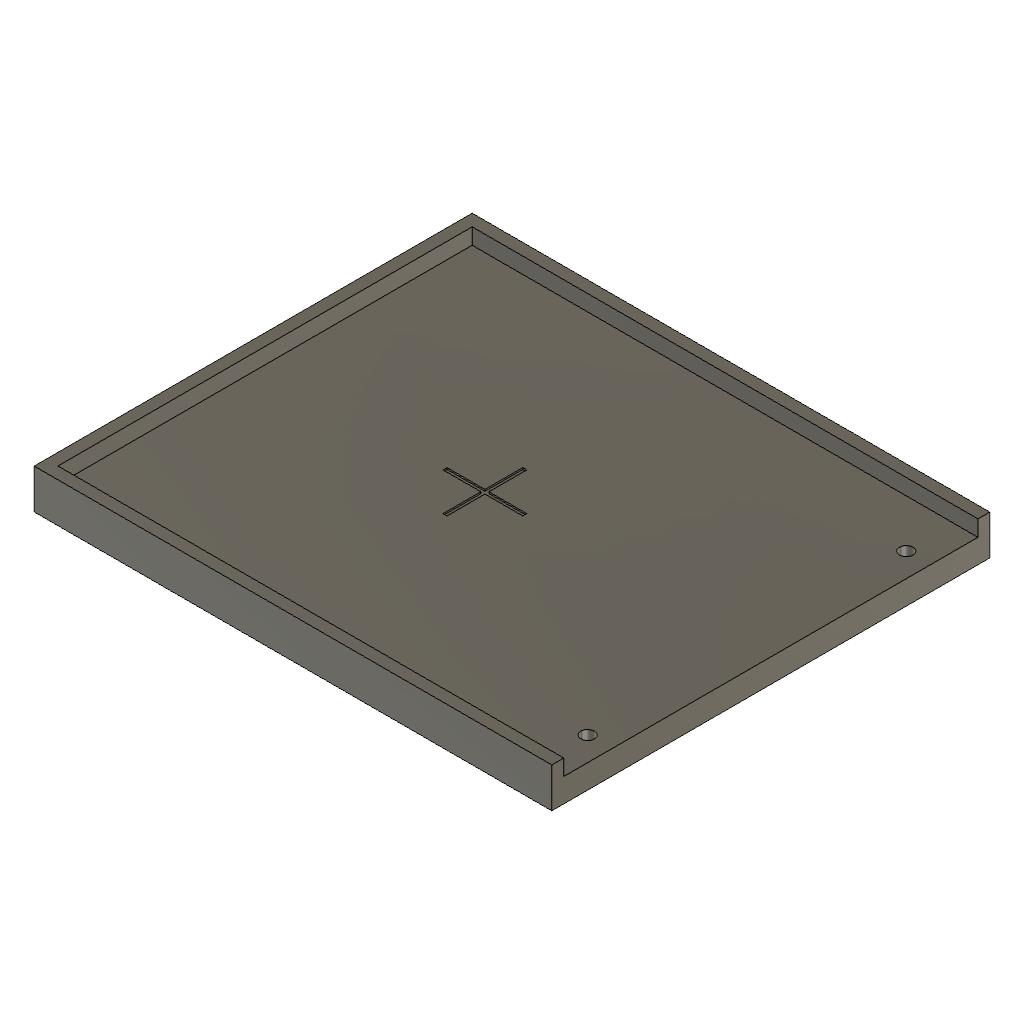
ballast_tray (Autodesk Fusion 360 design; units mm, degrees)
part number: 2026-10-11-03-14-11-502
Autodesk Fusion 360 part; units mm, degrees
sketch "Rear tray floor sketch" plane through (0, 0, 0) normal (0, 0, 1) x (1, 0, 0)
  line L0 (-104, -55) -> (26, -55)
  line L1 (26, -55) -> (26, 55)
  line L2 (26, 55) -> (-104, 55)
  line L3 (-104, 55) -> (-104, -55)
extrude "Rear tray floor" add sketch "Rear tray floor sketch" along normal blind 6
ref_plane "WorkPlane1" through (0, 0, 5.95) normal (0, 0, 1) x (1, 0, 0)
sketch "Rear weight stop sketch" plane through (0, 0, 5.95) normal (0, 0, 1) x (1, 0, 0)
  line L0 (-104, -55) -> (-101, -55)
  line L1 (-101, -55) -> (-101, 55)
  line L2 (-101, 55) -> (-104, 55)
  line L3 (-104, 55) -> (-104, -55)
extrude "Rear weight stop" add sketch "Rear weight stop sketch" along normal blind 4.05
ref_plane "WorkPlane2" through (0, 0, 5.95) normal (0, 0, 1) x (1, 0, 0)
sketch "Rear tray side lip -55 sketch" plane through (0, 0, 5.95) normal (0, 0, 1) x (1, 0, 0)
  line L0 (-104, -55) -> (26, -55)
  line L1 (26, -55) -> (26, -52)
  line L2 (26, -52) -> (-104, -52)
  line L3 (-104, -52) -> (-104, -55)
extrude "Rear tray side lip -55" add sketch "Rear tray side lip -55 sketch" along normal blind 4.05
ref_plane "WorkPlane3" through (0, 0, 5.95) normal (0, 0, 1) x (1, 0, 0)
sketch "Rear tray side lip 52 sketch" plane through (0, 0, 5.95) normal (0, 0, 1) x (1, 0, 0)
  line L0 (-104, 52) -> (26, 52)
  line L1 (26, 52) -> (26, 55)
  line L2 (26, 55) -> (-104, 55)
  line L3 (-104, 55) -> (-104, 52)
extrude "Rear tray side lip 52" add sketch "Rear tray side lip 52 sketch" along normal blind 4.05
ref_plane "WorkPlane4" through (0, 0, -0.05) normal (0, 0, 1) x (1, 0, 0)
sketch "Tray joint rear bolt -40 clearance sketch" plane through (0, 0, -0.05) normal (0, 0, 1) x (1, 0, 0)
  circle A0 centre (20, -40) radius 1.7
  dimension "d99" = 3.4
  measures "d99" diameter of A0
extrude "Tray joint rear bolt -40 clearance" cut sketch "Tray joint rear bolt -40 clearance sketch" along normal blind 6.1
ref_plane "WorkPlane5" through (0, 0, -0.05) normal (0, 0, 1) x (1, 0, 0)
sketch "Tray joint rear bolt -40 recessed head sketch" plane through (0, 0, -0.05) normal (0, 0, 1) x (1, 0, 0)
  circle A0 centre (20, -40) radius 3.2
  dimension "d104" = 6.4
  measures "d104" diameter of A0
extrude "Tray joint rear bolt -40 recessed head" cut sketch "Tray joint rear bolt -40 recessed head sketch" along normal blind 3.4
ref_plane "WorkPlane6" through (0, 0, -0.05) normal (0, 0, 1) x (1, 0, 0)
sketch "Tray joint rear bolt 40 clearance sketch" plane through (0, 0, -0.05) normal (0, 0, 1) x (1, 0, 0)
  circle A0 centre (20, 40) radius 1.7
  dimension "d109" = 3.4
  measures "d109" diameter of A0
extrude "Tray joint rear bolt 40 clearance" cut sketch "Tray joint rear bolt 40 clearance sketch" along normal blind 6.1
ref_plane "WorkPlane7" through (0, 0, -0.05) normal (0, 0, 1) x (1, 0, 0)
sketch "Tray joint rear bolt 40 recessed head sketch" plane through (0, 0, -0.05) normal (0, 0, 1) x (1, 0, 0)
  circle A0 centre (20, 40) radius 3.2
  dimension "d114" = 6.4
  measures "d114" diameter of A0
extrude "Tray joint rear bolt 40 recessed head" cut sketch "Tray joint rear bolt 40 recessed head sketch" along normal blind 3.4
ref_plane "WorkPlane8" through (0, 0, 5.6) normal (0, 0, 1) x (1, 0, 0)
sketch "Weight center line X sketch" plane through (0, 0, 5.6) normal (0, 0, 1) x (1, 0, 0)
  line L0 (-46.3, -10) -> (-45.3, -10)
  line L1 (-45.3, -10) -> (-45.3, 10)
  line L2 (-45.3, 10) -> (-46.3, 10)
  line L3 (-46.3, 10) -> (-46.3, -10)
extrude "Weight center line X" cut sketch "Weight center line X sketch" along normal blind 0.5
ref_plane "WorkPlane9" through (0, 0, 5.6) normal (0, 0, 1) x (1, 0, 0)
sketch "Weight center line Y sketch" plane through (0, 0, 5.6) normal (0, 0, 1) x (1, 0, 0)
  line L0 (-55.8, -0.5) -> (-35.8, -0.5)
  line L1 (-35.8, -0.5) -> (-35.8, 0.5)
  line L2 (-35.8, 0.5) -> (-55.8, 0.5)
  line L3 (-55.8, 0.5) -> (-55.8, -0.5)
extrude "Weight center line Y" cut sketch "Weight center line Y sketch" along normal blind 0.5
equation "d83 = standFloor"
equation "d99 = m3Clearance"
equation "d104 = m3HeadClearance"
equation "d109 = m3Clearance"
equation "d114 = m3HeadClearance"
equation "m3Clearance = 3.4 mm" comment "Weighted stand"
equation "m3HeadClearance = 6.4 mm" comment "Weighted stand"
equation "standFloor = 6 mm" comment "Weighted stand"
named bodies: "ballast_tray native printable solid"
